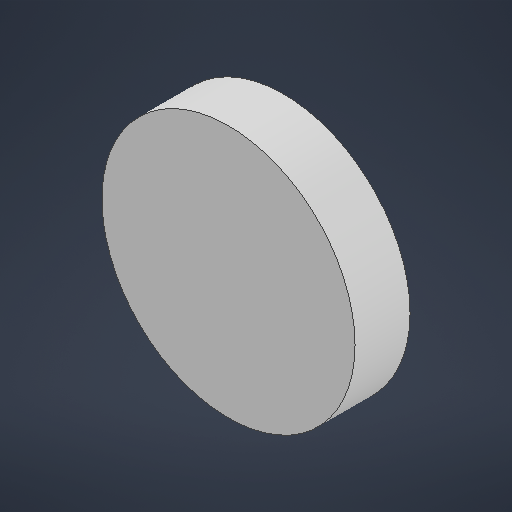
# Autodesk Inventor part: dummy_speaker23
Saved by Autodesk Inventor 2027.1 (Build 311270010, 270A)
## iProperties
Created: 2026-10-29
Part Number: dummy_speaker23
Material: Generic
Document SubType Name: Modeling
Designer: shyan
Density: 1 g/cm^3
Appearance: Default
Author: shyan
Autodesk Inventor part; units mm, degrees
ref_plane "YZ Plane" through (0, 0, 0) normal (1, 0, 0) x (0, 1, 0)
ref_plane "XZ Plane" through (0, 0, 0) normal (0, 1, 0) x (-1, 0, 0)
ref_plane "XY Plane" through (0, 0, 0) normal (0, 0, 1) x (1, 0, 0)
sketch "Sketch1" plane through (0, 0, 0) normal (0, 0, 1) x (1, 0, 0)
  circle A0 centre (0, 0) radius 11.5
  dimension "d0" = 5
  constraints: 1 centre point
extrude "Body" add sketch "Sketch1" along normal blind 5
body "Solid1"
